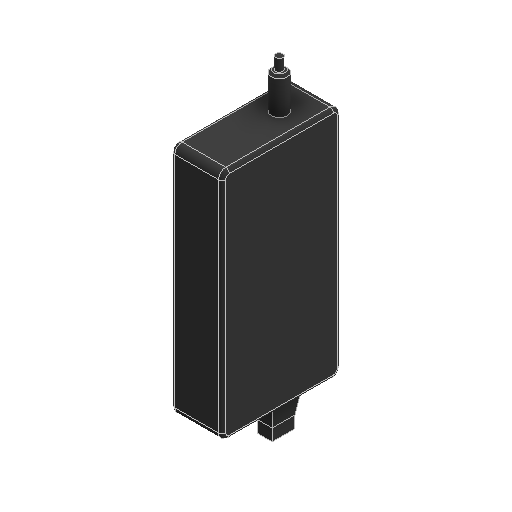
# Autodesk Inventor part: COTS_GENERIC_24V_Power_Brick
Saved by Autodesk Inventor 2027 (Build 310192060, 192F)
## iProperties
Created: 2026-03-01
Part Number: COTS_GENERIC_24V_Power_Brick
Material: Generic
Document SubType Name: Modeling
Designer: User
Density: 1 g/cm^3
Appearance: Rubber - Black
Author: User
Autodesk Inventor part; units mm, degrees
ref_plane "YZ Plane" through (0, 0, 0) normal (1, 0, 0) x (0, 1, 0)
ref_plane "XZ Plane" through (0, 0, 0) normal (0, 1, 0) x (-1, 0, 0)
ref_plane "XY Plane" through (0, 0, 0) normal (0, 0, 1) x (1, 0, 0)
sketch "Sketch1" plane through (0, 0, 0) normal (0, 1, 0) x (-1, 0, 0)
  line L0 (21.25, 49.5) -> (-21.25, 49.5)
  line L1 (-21.25, 49.5) -> (-21.25, -49.5)
  line L2 (-21.25, -49.5) -> (21.25, -49.5)
  line L3 (21.25, -49.5) -> (21.25, 49.5)
  point P0 (0, 0)
  dimension "d0" = 99
  dimension "d1" = 42.5
  dimension "d2" = 21.25
  dimension "d3" = 49.5
  constraints: 8 end point, 2 parallel, 1 horizontal, 1 perpendicular
  measures "d0" distance of L0.end L1.end
  measures "d1" distance of L0.start L0.end
  measures "d2" distance from line of point (0, 0) L3
  measures "d3" distance from line of L0 point (0, 0)
extrude "Extrusion1" add sketch "Sketch1" along normal blind 195
fillet "Fillet1" radius 6 4 edges at (0, 195, 49.5) (0, 195, -49.5) (0, 0, 49.5) (0, 0, -49.5)
fillet "Fillet2" radius 3 16 edges at (-21.25, 193.2426, 47.7426) (-21.25, 195, 0) (-21.25, 193.2426, -47.7426) (-21.25, 97.5, -49.5) (-21.25, 1.7574, -47.7426) (-21.25, 0, 0) (-21.25, 1.7574, 47.7426) (-21.25, 97.5, 49.5) (21.25, 193.2426, 47.7426) (21.25, 195, 0) (21.25, 193.2426, -47.7426) (21.25, 97.5, -49.5) (21.25, 1.7574, -47.7426) (21.25, 0, 0) (21.25, 1.7574, 47.7426) (21.25, 97.5, 49.5)
sketch "Sketch2" plane through (0, 195, 0) normal (0, 1, 0) x (1, 0, 0)
  circle A0 centre (0, 19.5) radius 6.75
  line L0 (18.25, 49.5) -> (-18.25, 49.5) projected
  point P0 (0, 0)
  dimension "d8" = 13.5
  dimension "d9" = 30
  constraints: 1 centre point
  measures "d8" diameter of A0
  measures "d9" distance from line of A0.centre L0
extrude "Extrusion2" add sketch "Sketch2" along normal blind 30
sketch "Sketch3" plane through (0, 225, -19.5) normal (0, 1, 0) x (1, 0, 0)
  circle A0 centre (0, 0) radius 6.75 projected
  circle A1 centre (0, 0) radius 3
  point P0 (0, -19.5)
  dimension "d12" = 6
  constraints: 1 centre point, 1 coincident
  measures "d12" diameter of A1
extrude "Extrusion3" add sketch "Sketch3" along normal blind 10 contours A1
sketch "Sketch4" plane through (0, 0, 0) normal (0, -1, 0) x (1, 0, 0)
  line L0 (9, -4.5) -> (-9, -4.5)
  line L1 (-9, -4.5) -> (-9, -29.5)
  line L2 (-9, -29.5) -> (9, -29.5)
  line L3 (9, -29.5) -> (9, -4.5)
  line L4 (-18.25, -49.5) -> (18.25, -49.5) projected
  point P0 (0, 0)
  dimension "d15" = 25
  dimension "d16" = 18
  dimension "d17" = 9
  dimension "d18" = 20
  constraints: 8 end point, 2 parallel, 1 horizontal, 1 perpendicular
  measures "d15" distance between parallel lines of L2 L0
  measures "d16" distance of L0.start L0.end
  measures "d17" distance from line of point (0, 0) L3
  measures "d18" distance between parallel lines of L4 L2
extrude "Extrusion4" add sketch "Sketch4" along normal blind 25
chamfer "Chamfer1" distance 3 distance2 20 4 edges at (9, -25, -17) (0, -25, -29.5) (-9, -25, -17) (0, -25, -4.5) measured on face at (0, -25, -5) measured on face at (8.5, -25, -17) measured on face at (-8.5, -25, -17) measured on face at (0, -25, -29)
chamfer "Chamfer2" distance 2 angle 45 1 edges at (-6.75, 225, -19.5)
sketch "Sketch5" plane through (0, -25, 0) normal (0, -1, 0) x (1, 0, 0)
  line L0 (-6, -26.5) -> (-6, -7.5) projected
  line L1 (6, -26.5) -> (-6, -26.5) projected
  line L2 (6, -7.5) -> (6, -26.5) projected
  line L3 (-6, -7.5) -> (6, -7.5) projected
  point P0 (0, 0)
extrude "Extrusion5" add sketch "Sketch5" along normal blind 10
equation "\"d2\" = 0.5 * d1"
equation "\"d3\" = 0.5 * d0"
equation "\"d17\" = 0.5 * d16"
body "Solid1"
